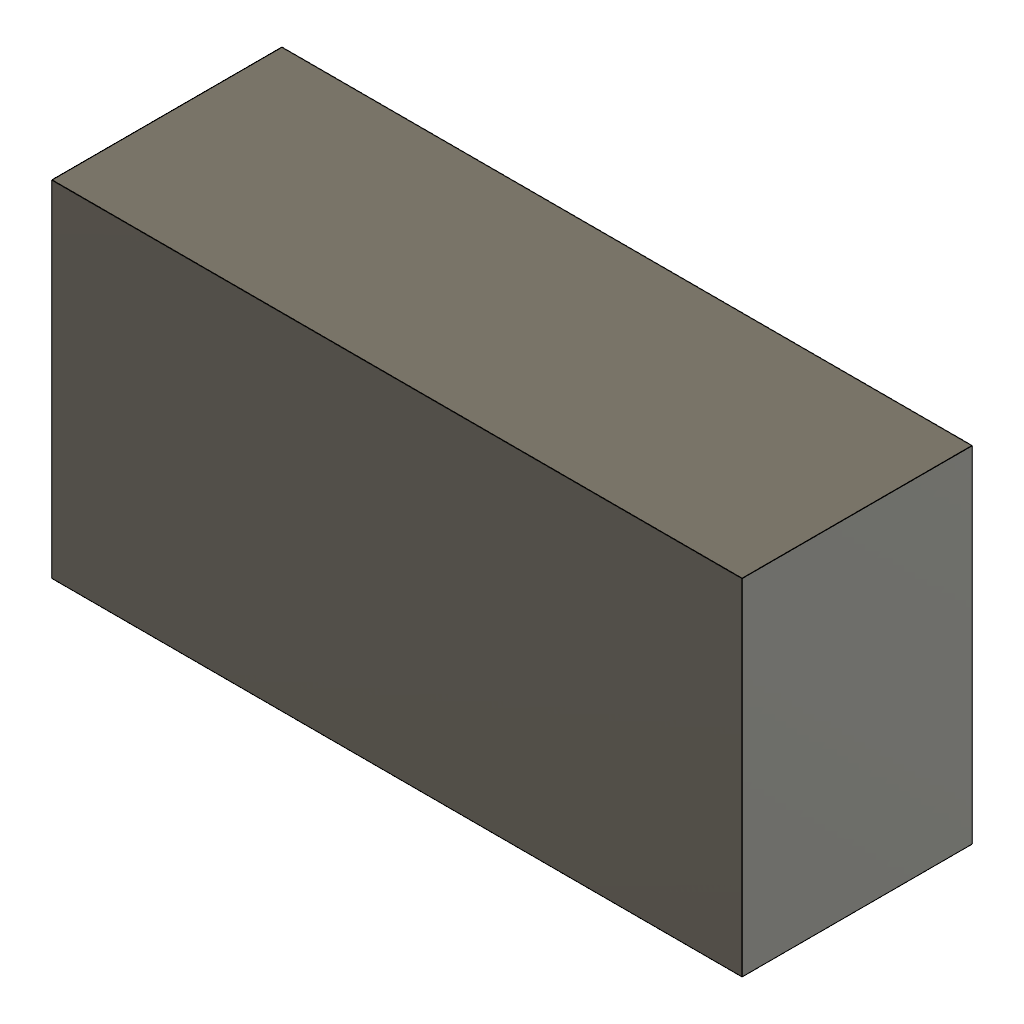
sk_dimension_params (Autodesk Fusion 360 design; units mm, degrees)
part number: 2026-11-13-14-35-38-038
Autodesk Fusion 360 part; units mm, degrees
sketch "Sketch1" plane through (0, 0, 0) normal (0, 0, 1) x (1, 0, 0)
  line L0 (0, 0) -> (30, 0)
  line L1 (30, 0) -> (30, 15)
  line L2 (30, 15) -> (0, 15)
  line L3 (0, 15) -> (0, 0)
  dimension "d3" = 30
  dimension "d4" = 15
  measures "d3" horizontal distance of L0.start L0.end
  measures "d4" vertical distance of L0.end L1.end
extrude "Extrude1" add sketch "Sketch1" along normal blind 10
equation "w = 30 mm"
equation "h = 15 mm"
equation "d3 = w"
equation "d4 = h"
equation "d5 = w / 3"
